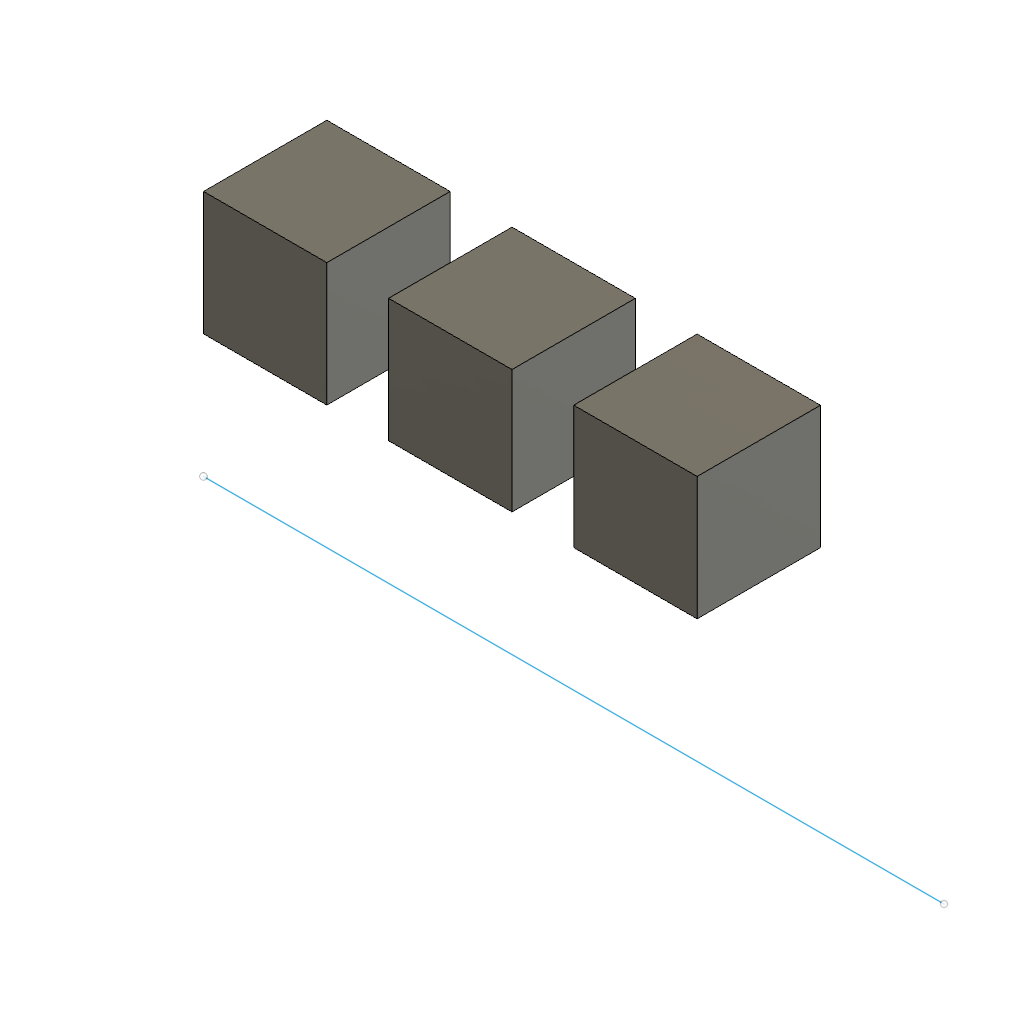
root_occurrence (Autodesk Fusion 360 design; units mm, degrees)
part number: 2026-10-21-12-26-45-132
part number: 2026-10-21-12-26-45-324
Autodesk Fusion 360 part; units mm, degrees
sketch "PathPatternSeedProfile" plane through (0, 0, 0) normal (0, 0, 1) x (1, 0, 0) in component "PathPatternSourceComponent"
  line L0 (0, 0) -> (10, 0)
  line L1 (10, 0) -> (10, 10)
  line L2 (10, 10) -> (0, 10)
  line L3 (0, 10) -> (0, 0)
extrude "PathPatternSeedExtrude" add sketch "PathPatternSeedProfile" along normal blind 10 in component "PathPatternSourceComponent"
sketch "InputContrastStraightPath" plane through (0, 0, 0) normal (0, 0, 1) x (1, 0, 0)
  line L0 (0, 0) -> (60, 0)
component_pattern "ProbePathPatternRootOccurrence"
component "PathPatternSourceComponent" placed x (1, 0, 0) y (0, 1, 0) z (0, 0, 1) at (10, 20, 0)
component "PathPatternSourceComponent" placed x (1, 0, 0) y (0, 1, 0) z (0, 0, 1) at (25, 20, 0)
component "PathPatternSourceComponent" placed x (1, 0, 0) y (0, 1, 0) z (0, 0, 1) at (40, 20, 0)
named bodies: "PathPatternSeedBody"
